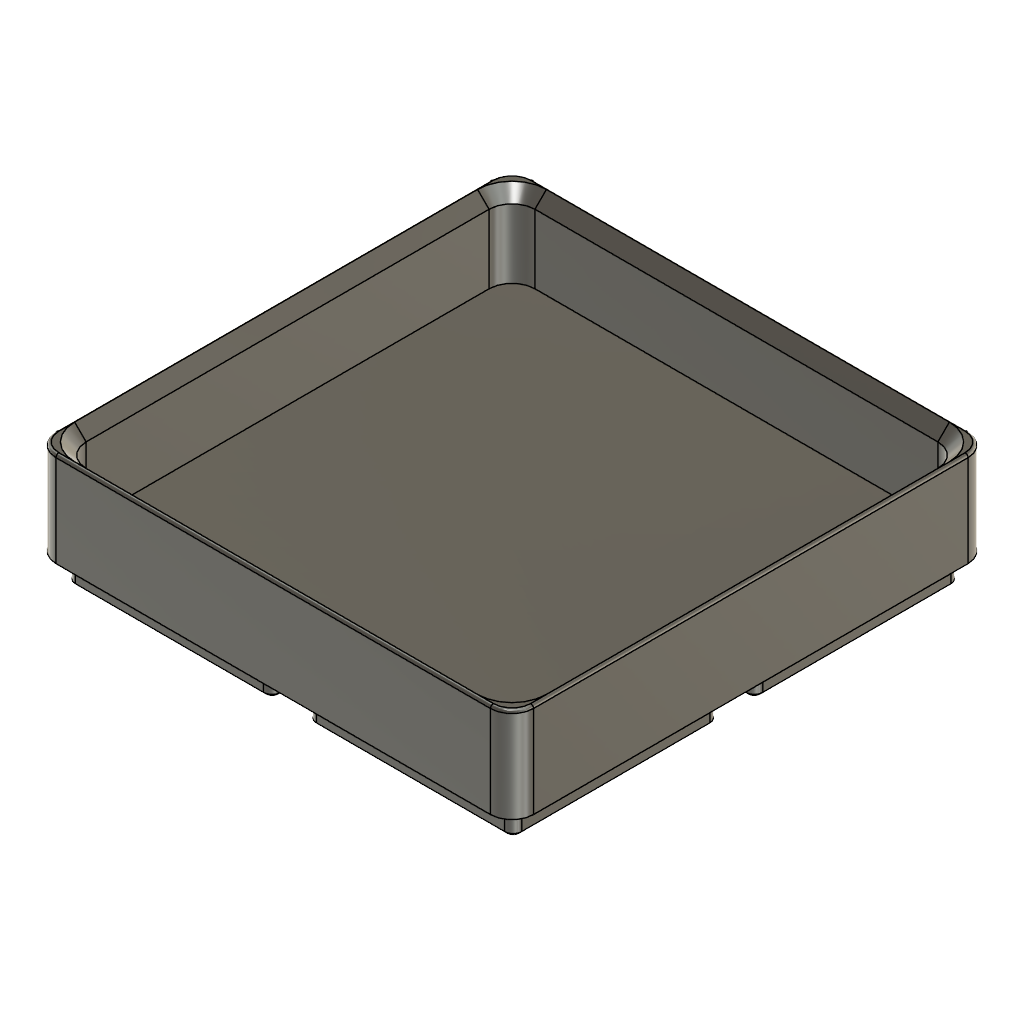
valjundhoidik-v1 (Autodesk Fusion 360 design; units mm, degrees)
part number: 2026-10-03-11-57-42-661
Autodesk Fusion 360 part; units mm, degrees
sketch "Sketch_OuterProfile" plane through (0, 0, 0) normal (0, 0, 1) x (1, 0, 0)
  line L0 (41.6, 41.6) -> (-41.6, 41.6)
  line L1 (-41.6, 41.6) -> (-41.6, -41.6)
  line L2 (-41.6, -41.6) -> (41.6, -41.6)
  line L3 (41.6, -41.6) -> (41.6, 41.6)
  dimension "d26" = 83.2
  dimension "d27" = 83.2
  measures "d26" horizontal distance of L0.start L0.end
  measures "d27" vertical distance of L0.end L1.end
extrude "Extrude_Body" add sketch "Sketch_OuterProfile" along normal blind 16.5
fillet "Fillet_OuterVerticalEdges" radius 3.75 4 edges at (41.6, -41.6, 8.25) (-41.6, -41.6, 8.25) (-41.6, 41.6, 8.25) (41.6, 41.6, 8.25)
fillet "Fillet_TopOuterEdge" radius 0.5 64 edges at (40.5017, 40.5017, 16.5) (41.6, 0, 16.5) (40.5017, -40.5017, 16.5) (0, -41.6, 16.5) (-40.5017, -40.5017, 16.5) (-41.6, 0, 16.5) (-40.5017, 40.5017, 16.5) (0, 41.6, 16.5) (0, 41.6, 16.5) (-40.5017, 40.5017, 16.5) (-41.6, 0, 16.5) (-40.5017, -40.5017, 16.5) (0, -41.6, 16.5) (40.5017, -40.5017, 16.5) (41.6, 0, 16.5) (40.5017, 40.5017, 16.5) (-40.5017, 40.5017, 16.5) (0, 41.6, 16.5) (40.5017, 40.5017, 16.5) (41.6, 0, 16.5) (40.5017, -40.5017, 16.5) (0, -41.6, 16.5) (-40.5017, -40.5017, 16.5) (-41.6, 0, 16.5) (-41.6, 0, 16.5) (-40.5017, -40.5017, 16.5) (0, -41.6, 16.5) (40.5017, -40.5017, 16.5) (41.6, 0, 16.5) (40.5017, 40.5017, 16.5) (0, 41.6, 16.5) (-40.5017, 40.5017, 16.5) (-40.5017, -40.5017, 16.5) (-41.6, 0, 16.5) (-40.5017, 40.5017, 16.5) (0, 41.6, 16.5) (40.5017, 40.5017, 16.5) (41.6, 0, 16.5) (40.5017, -40.5017, 16.5) (0, -41.6, 16.5) (0, -41.6, 16.5) (40.5017, -40.5017, 16.5) (41.6, 0, 16.5) (40.5017, 40.5017, 16.5) (0, 41.6, 16.5) (-40.5017, 40.5017, 16.5) (-41.6, 0, 16.5) (-40.5017, -40.5017, 16.5) (40.5017, -40.5017, 16.5) (0, -41.6, 16.5) (-40.5017, -40.5017, 16.5) (-41.6, 0, 16.5) (-40.5017, 40.5017, 16.5) (0, 41.6, 16.5) (40.5017, 40.5017, 16.5) (41.6, 0, 16.5) (41.6, 0, 16.5) (40.5017, 40.5017, 16.5) (0, 41.6, 16.5) (-40.5017, 40.5017, 16.5) (-41.6, 0, 16.5) (-40.5017, -40.5017, 16.5) (0, -41.6, 16.5) (40.5017, -40.5017, 16.5)
ref_plane "WorkPlane1" through (0, 0, 16.5) normal (0, 0, 1) x (1, 0, 0)
sketch "Sketch_Pocket_1" plane through (0, 0, 16.5) normal (0, 0, 1) x (1, 0, 0)
  line L0 (-5.7, -5.7) -> (-36.3, -5.7)
  line L1 (-36.3, -5.7) -> (-36.3, -36.3)
  line L2 (-36.3, -36.3) -> (-5.7, -36.3)
  line L3 (-5.7, -36.3) -> (-5.7, -5.7)
  dimension "d37" = 30.6
  dimension "d38" = 30.6
  measures "d37" horizontal distance of L0.start L0.end
  measures "d38" vertical distance of L0.end L1.end
extrude "Extrude_Pocket_1" [suppressed]
sketch "Sketch_FingerAccessX_1" plane through (0, 0, 16.5) normal (0, 0, 1) x (1, 0, 0)
  circle A0 centre (-36.3, -21) radius 6
extrude "Extrude_FingerAccessX_1" [suppressed]
sketch "Sketch_FingerAccessY_1" plane through (0, 0, 16.5) normal (0, 0, 1) x (1, 0, 0)
  circle A0 centre (-21, -36.3) radius 6
extrude "Extrude_FingerAccessY_1" [suppressed]
sketch "Sketch_Pocket_2" plane through (0, 0, 16.5) normal (0, 0, 1) x (1, 0, 0)
  line L0 (-5.7, 36.3) -> (-36.3, 36.3)
  line L1 (-36.3, 36.3) -> (-36.3, 5.7)
  line L2 (-36.3, 5.7) -> (-5.7, 5.7)
  line L3 (-5.7, 5.7) -> (-5.7, 36.3)
  dimension "d45" = 30.6
  dimension "d46" = 30.6
  measures "d45" horizontal distance of L0.start L0.end
  measures "d46" vertical distance of L0.end L1.end
extrude "Extrude_Pocket_2" [suppressed]
sketch "Sketch_FingerAccessX_2" plane through (0, 0, 16.5) normal (0, 0, 1) x (1, 0, 0)
  circle A0 centre (-36.3, 21) radius 6
extrude "Extrude_FingerAccessX_2" [suppressed]
sketch "Sketch_FingerAccessY_2" plane through (0, 0, 16.5) normal (0, 0, 1) x (1, 0, 0)
  circle A0 centre (-21, 36.3) radius 6
extrude "Extrude_FingerAccessY_2" [suppressed]
sketch "Sketch_Pocket_3" plane through (0, 0, 16.5) normal (0, 0, 1) x (1, 0, 0)
  line L0 (36.3, -5.7) -> (5.7, -5.7)
  line L1 (5.7, -5.7) -> (5.7, -36.3)
  line L2 (5.7, -36.3) -> (36.3, -36.3)
  line L3 (36.3, -36.3) -> (36.3, -5.7)
  dimension "d53" = 30.6
  dimension "d54" = 30.6
  measures "d53" horizontal distance of L0.start L0.end
  measures "d54" vertical distance of L0.end L1.end
extrude "Extrude_Pocket_3" [suppressed]
sketch "Sketch_FingerAccessX_3" plane through (0, 0, 16.5) normal (0, 0, 1) x (1, 0, 0)
  circle A0 centre (36.3, -21) radius 6
extrude "Extrude_FingerAccessX_3" [suppressed]
sketch "Sketch_FingerAccessY_3" plane through (0, 0, 16.5) normal (0, 0, 1) x (1, 0, 0)
  circle A0 centre (21, -36.3) radius 6
extrude "Extrude_FingerAccessY_3" [suppressed]
sketch "Sketch_Pocket_4" plane through (0, 0, 16.5) normal (0, 0, 1) x (1, 0, 0)
  line L0 (36.3, 36.3) -> (5.7, 36.3)
  line L1 (5.7, 36.3) -> (5.7, 5.7)
  line L2 (5.7, 5.7) -> (36.3, 5.7)
  line L3 (36.3, 5.7) -> (36.3, 36.3)
  dimension "d61" = 30.6
  dimension "d62" = 30.6
  measures "d61" horizontal distance of L0.start L0.end
  measures "d62" vertical distance of L0.end L1.end
extrude "Extrude_Pocket_4" [suppressed]
sketch "Sketch_FingerAccessX_4" plane through (0, 0, 16.5) normal (0, 0, 1) x (1, 0, 0)
  circle A0 centre (36.3, 21) radius 6
extrude "Extrude_FingerAccessX_4" [suppressed]
sketch "Sketch_FingerAccessY_4" plane through (0, 0, 16.5) normal (0, 0, 1) x (1, 0, 0)
  circle A0 centre (21, 36.3) radius 6
extrude "Extrude_FingerAccessY_4" [suppressed]
sketch "Sketch_Foot_1" plane through (0, 0, 0) normal (0, 0, 1) x (1, 0, 0)
  line L0 (-3.01, -3.01) -> (-38.79, -3.01)
  line L1 (-38.79, -3.01) -> (-38.79, -38.79)
  line L2 (-38.79, -38.79) -> (-3.01, -38.79)
  line L3 (-3.01, -38.79) -> (-3.01, -3.01)
  dimension "d77" = 35.78
  dimension "d78" = 35.78
  measures "d77" horizontal distance of L0.start L0.end
  measures "d78" vertical distance of L0.end L1.end
extrude "Extrude_Foot_1" add sketch "Sketch_Foot_1" against normal blind 4.65
fillet "Fillet_FootEdges_1" radius 1.5 4 edges at (-3.01, -3.01, -2.325) (-38.79, -3.01, -2.325) (-38.79, -38.79, -2.325) (-3.01, -38.79, -2.325)
sketch "Sketch_Foot_2" plane through (0, 0, 0) normal (0, 0, 1) x (1, 0, 0)
  line L0 (-3.01, 38.99) -> (-38.79, 38.99)
  line L1 (-38.79, 38.99) -> (-38.79, 3.21)
  line L2 (-38.79, 3.21) -> (-3.01, 3.21)
  line L3 (-3.01, 3.21) -> (-3.01, 38.99)
  dimension "d83" = 35.78
  dimension "d84" = 35.78
  measures "d83" horizontal distance of L0.start L0.end
  measures "d84" vertical distance of L0.end L1.end
extrude "Extrude_Foot_2" add sketch "Sketch_Foot_2" against normal blind 4.65
fillet "Fillet_FootEdges_2" radius 1.5 4 edges at (-3.01, 38.99, -2.325) (-38.79, 38.99, -2.325) (-38.79, 3.21, -2.325) (-3.01, 3.21, -2.325)
sketch "Sketch_Foot_3" plane through (0, 0, 0) normal (0, 0, 1) x (1, 0, 0)
  line L0 (38.99, -3.01) -> (3.21, -3.01)
  line L1 (3.21, -3.01) -> (3.21, -38.79)
  line L2 (3.21, -38.79) -> (38.99, -38.79)
  line L3 (38.99, -38.79) -> (38.99, -3.01)
  dimension "d89" = 35.78
  dimension "d90" = 35.78
  measures "d89" horizontal distance of L0.start L0.end
  measures "d90" vertical distance of L0.end L1.end
extrude "Extrude_Foot_3" add sketch "Sketch_Foot_3" against normal blind 4.65
fillet "Fillet_FootEdges_3" radius 1.5 4 edges at (38.99, -3.01, -2.325) (3.21, -3.01, -2.325) (3.21, -38.79, -2.325) (38.99, -38.79, -2.325)
sketch "Sketch_Foot_4" plane through (0, 0, 0) normal (0, 0, 1) x (1, 0, 0)
  line L0 (38.99, 38.99) -> (3.21, 38.99)
  line L1 (3.21, 38.99) -> (3.21, 3.21)
  line L2 (3.21, 3.21) -> (38.99, 3.21)
  line L3 (38.99, 3.21) -> (38.99, 38.99)
  dimension "d95" = 35.78
  dimension "d96" = 35.78
  measures "d95" horizontal distance of L0.start L0.end
  measures "d96" vertical distance of L0.end L1.end
extrude "Extrude_Foot_4" add sketch "Sketch_Foot_4" against normal blind 4.65
fillet "Fillet_FootEdges_4" radius 1.5 4 edges at (38.99, 38.99, -2.325) (3.21, 38.99, -2.325) (3.21, 3.21, -2.325) (38.99, 3.21, -2.325)
extrude "Extrude18" [suppressed]
sketch "Sketch_OutputCavity" plane through (0, 0, 0) normal (0, 0, 1) x (1, 0, 0)
  line L0 (-39.1, -39.1) -> (39.1, -39.1)
  line L1 (39.1, -39.1) -> (39.1, 39.1)
  line L2 (39.1, 39.1) -> (-39.1, 39.1)
  line L3 (-39.1, 39.1) -> (-39.1, -39.1)
  dimension "d115" = 39.1
  dimension "d116" = 39.1
  dimension "d117" = 39.1
  dimension "d118" = 39.1
  measures "d115" horizontal distance of origin L1.end
  measures "d116" vertical distance of origin L1.end
  measures "d117" horizontal distance of origin L0.start
  measures "d118" vertical distance of origin L0.start
extrude "Extrude_OutputCavity" cut sketch "Sketch_OutputCavity" against normal blind 14 from surface at 16.5
fillet "Fillet_OutputCavityCorners" radius 4 4 edges at (-39.1, 39.1, 9.5) (39.1, 39.1, 9.5) (-39.1, -39.1, 9.5) (39.1, -39.1, 9.5)
chamfer "Chamfer_OutputLeadIn" distance 2 angle 45 8 edges at (37.9284, -37.9284, 16.5) (39.1, 0, 16.5) (37.9284, 37.9284, 16.5) (0, 39.1, 16.5) (-37.9284, 37.9284, 16.5) (-39.1, 0, 16.5) (-37.9284, -37.9284, 16.5) (0, -39.1, 16.5) tangent chain off
chamfer "Chamfer_FootBottom" distance 0.5 angle 45 32 edges at (38.5507, 3.6493, -4.65) (38.99, 21.1, -4.65) (38.5507, 38.5507, -4.65) (21.1, 38.99, -4.65) (3.6493, 38.5507, -4.65) (3.21, 21.1, -4.65) (3.6493, 3.6493, -4.65) (21.1, 3.21, -4.65) (38.5507, -38.3507, -4.65) (38.99, -20.9, -4.65) (38.5507, -3.4493, -4.65) (21.1, -3.01, -4.65) (3.6493, -3.4493, -4.65) (3.21, -20.9, -4.65) (3.6493, -38.3507, -4.65) (21.1, -38.79, -4.65) (-3.4493, 3.6493, -4.65) (-3.01, 21.1, -4.65) (-3.4493, 38.5507, -4.65) (-20.9, 38.99, -4.65) (-38.3507, 38.5507, -4.65) (-38.79, 21.1, -4.65) (-38.3507, 3.6493, -4.65) (-20.9, 3.21, -4.65) (-3.4493, -38.3507, -4.65) (-3.01, -20.9, -4.65) (-3.4493, -3.4493, -4.65) (-20.9, -3.01, -4.65) (-38.3507, -3.4493, -4.65) (-38.79, -20.9, -4.65) (-38.3507, -38.3507, -4.65) (-20.9, -38.79, -4.65) tangent chain off
equation "grid_pitch = 42 mm" comment "Gridfinity grid pitch (standard, per MG400 rig doc)"
equation "grid_clearance = 0.3 mm" comment "Fit clearance measured in Lab 1 (range 0.2-0.4 mm, chosen 0.3 mm)"
equation "gf_outer_offset = 0.5 mm" comment "Standard Gridfinity outer undersize per cell (42n - 0.5)"
equation "gf_corner_radius = 3.75 mm" comment "Standard Gridfinity outer vertical corner radius"
equation "gf_foot_chamfer_bottom = 0.8 mm" comment "Gridfinity foot: bottom 45deg segment height (reference)"
equation "gf_foot_vertical = 1.8 mm" comment "Gridfinity foot: vertical segment height (reference)"
equation "gf_foot_chamfer_top = 2.15 mm" comment "Gridfinity foot: top 45deg segment height (reference)"
equation "foot_lead_in_chamfer = gf_foot_chamfer_bottom + gf_foot_chamfer_top" comment "Simplified single lead-in chamfer approximating the Gridfinity foot flare"
equation "grid_cols = 2" comment "Number of Gridfinity cells in X (build-time layout parameter)"
equation "grid_rows = 2" comment "Number of Gridfinity cells in Y (build-time layout parameter)"
equation "glass_width = 30 mm" comment "Polycarbonate glass piece width (given)"
equation "glass_length = 30 mm" comment "Polycarbonate glass piece length (given)"
equation "glass_thickness = 2 mm" comment "Polycarbonate glass piece thickness (given)"
equation "part_clearance = 0.3 mm" comment "Printer fit clearance measured in Lab 1, applied per side between glass and pocket"
equation "pocket_width = glass_width + 2 * part_clearance" comment "Pocket opening width (glass width plus clearance both sides)"
equation "pocket_length = glass_length + 2 * part_clearance" comment "Pocket opening length (glass length plus clearance both sides)"
equation "reveal_height = 0.5 mm" comment "ASSUMPTION: how far the glass protrudes above the holder top surface for suction-cup and finger access"
equation "pocket_depth = glass_thickness - reveal_height" comment "Pocket depth, kept shallow so the glass top stays exposed"
equation "floor_thickness = 4 mm" comment "ASSUMPTION: solid floor thickness beneath the pocket"
equation "holder_height = out_floor_thickness + out_cavity_depth" comment "Total external height of the holder (kept low, no high walls)"
equation "holder_outer_x = grid_pitch * grid_cols - gf_outer_offset - grid_clearance" comment "Outer footprint in X, derived from cell count"
equation "holder_outer_y = grid_pitch * grid_rows - gf_outer_offset - grid_clearance" comment "Outer footprint in Y, derived from cell count"
equation "lead_in_chamfer = 0.5 mm" comment "ASSUMPTION: small chamfer around each pocket opening to ease glass insertion (reduced size for this thin, shallow tray)"
equation "top_edge_fillet_radius = 0.5 mm" comment "ASSUMPTION: small deburr fillet on the top outer rim (reduced from standard Gridfinity radius since this part is very thin)"
equation "finger_cutout_radius = 6 mm" comment "ASSUMPTION: radius of the finger-access scallop cut into two outward-facing sides of each pocket"
equation "d26 = holder_outer_x"
equation "d27 = holder_outer_y"
equation "d28 = holder_height"
equation "d31 = gf_corner_radius"
equation "d34 = top_edge_fillet_radius"
equation "d35 = holder_height"
equation "d37 = pocket_width"
equation "d38 = pocket_length"
equation "d39 = -pocket_depth"
equation "d41 = -pocket_depth"
equation "d43 = -pocket_depth"
equation "d45 = pocket_width"
equation "d46 = pocket_length"
equation "d47 = -pocket_depth"
equation "d49 = -pocket_depth"
equation "d51 = -pocket_depth"
equation "d53 = pocket_width"
equation "d54 = pocket_length"
equation "d55 = -pocket_depth"
equation "d57 = -pocket_depth"
equation "d59 = -pocket_depth"
equation "d61 = pocket_width"
equation "d62 = pocket_length"
equation "d63 = -pocket_depth"
equation "d65 = -pocket_depth"
equation "d67 = -pocket_depth"
equation "gf_socket_mouth_size = 41.98 mm" comment "MEASURED from MG400 rakis grid_pos_0: top opening of real baseplate socket"
equation "gf_socket_mid_size = 37.68 mm" comment "MEASURED: socket width after top chamfer segment"
equation "gf_socket_floor_size = 36.28 mm" comment "MEASURED: narrowest width at socket floor"
equation "gf_socket_depth = 4.65 mm" comment "MEASURED: real socket depth (0.70 + 1.80 + 2.15 mm segments), corrects earlier 4.75 mm assumption"
equation "foot_size = gf_socket_floor_size - 2 * foot_clearance" comment "Constant-width foot: narrowest socket width minus clearance on both sides"
equation "foot_depth = gf_socket_depth" comment "Foot protrusion depth below the main floor, matches measured socket depth"
equation "foot_corner_radius = gf_socket_floor_corner_radius + 0.36 mm" comment "Foot corner radius kept larger than the socket throat radius (1.14 mm), so the corners never touch first (v1 used 0.5 mm and jammed at the corners)"
equation "total_height_with_feet = holder_height + foot_depth" comment "Overall height including protruding feet, for reference"
equation "d77 = foot_size"
equation "d78 = foot_size"
equation "d79 = -foot_depth"
equation "d82 = foot_corner_radius"
equation "d83 = foot_size"
equation "d84 = foot_size"
equation "d85 = -foot_depth"
equation "d88 = foot_corner_radius"
equation "d89 = foot_size"
equation "d90 = foot_size"
equation "d91 = -foot_depth"
equation "d94 = foot_corner_radius"
equation "d95 = foot_size"
equation "d96 = foot_size"
equation "d97 = -foot_depth"
equation "d100 = foot_corner_radius"
equation "out_floor_thickness = 2.5 mm" comment "Output box: floor thickness under the open cavity"
equation "out_cavity_depth = 14 mm" comment "Output box: depth of the single open cavity (higher walls than the glass input tray, robot places less accurately)"
equation "out_wall_thickness = 2.5 mm" comment "Output box: side wall thickness"
equation "out_cavity_corner_radius = 4 mm" comment "Output box: inner vertical corner radius"
equation "out_lead_in = 2 mm" comment "Output box: 45deg lead-in chamfer on the inner top edge (bigger than input pockets)"
equation "d115 = ( holder_outer_x - 2 * out_wall_thickness ) / 2"
equation "d116 = ( holder_outer_y - 2 * out_wall_thickness ) / 2"
equation "d117 = ( holder_outer_x - 2 * out_wall_thickness ) / 2"
equation "d118 = ( holder_outer_y - 2 * out_wall_thickness ) / 2"
equation "d119 = holder_height"
equation "d120 = -( out_cavity_depth )"
equation "d123 = out_cavity_corner_radius"
equation "d124 = out_lead_in"
equation "gf_socket_floor_corner_radius = 1.14 mm" comment "MEASURED 23.10.26 in MG 400 rakis (grid_pos_0): corner radius of the narrowest socket section (36.28 mm, z +2.63)"
equation "foot_clearance = 0.25 mm" comment "Gap per side between foot and the narrowest socket section (was 0.15 mm per side in v1, too tight with first-layer squish)"
equation "foot_bottom_chamfer = 0.5 mm" comment "45deg chamfer on the foot bottom edge: lead-in into the socket and elephant-foot compensation"
equation "d128 = foot_bottom_chamfer"
named bodies: "GlassOutputBody"
